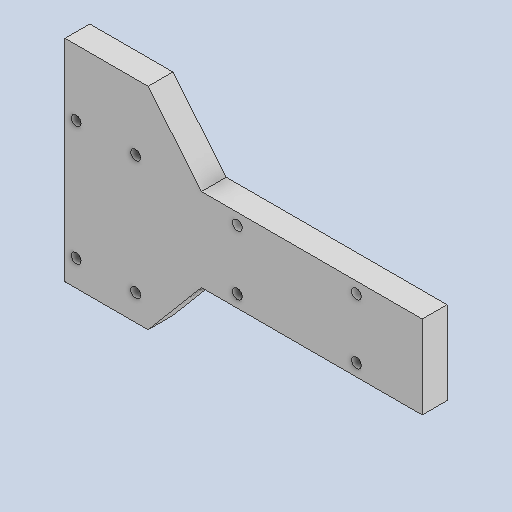
# Autodesk Inventor part: ConnectortoElbowSide
Saved by Autodesk Inventor 2025.2 (Build 292293000, 293)
## iProperties
Created: 2025-06-27
Part Number: ConnectortoElbowSide
Material: Generic
Document SubType Name: Modeling
Designer: ricoa
Density: 1 g/cm^3
Appearance: Default
Author: ricoa
Autodesk Inventor part; units mm, degrees
ref_plane "YZ Plane" through (0, 0, 0) normal (1, 0, 0) x (0, 1, 0)
ref_plane "XZ Plane" through (0, 0, 0) normal (0, 1, 0) x (-1, 0, 0)
ref_plane "XY Plane" through (0, 0, 0) normal (0, 0, 1) x (1, 0, 0)
sketch "Sketch1" plane through (0, 0, 0) normal (0, 0, 1) x (1, 0, 0)
  line L0 (-2, 0) -> (-2, 16.75) projected
  line L1 (-2, 16.75) -> (-44.5, 16.75) projected
  line L2 (-2, 0) -> (-44.5, 0) projected
  circle A0 centre (-39.25, 2.5) radius 1 projected
  circle A1 centre (-39.25, 14.5) radius 1 projected
  circle A2 centre (-15.25, 2.5) radius 1 projected
  circle A3 centre (-15.25, 14.5) radius 1 projected
  line L3 (-44.5, 16.75) -> (-46.5, 16.75)
  line L4 (-44.5, 0) -> (-46.5, 0)
  line L5 (-15.25, 14.5) -> (-8, 14.5)
  line L6 (-8, 16.75) -> (-8, 0)
  line L7 (-57.25, 29.75) -> (-74, 29.75) projected
  line L8 (-74, 29.75) -> (-74, -12.75) projected
  line L9 (-74, -12.75) -> (-57.25, -12.75) projected
  line L10 (-57.25, 29.75) -> (-57.25, -12.75)
  circle A4 centre (-59.75, -7.5) radius 1 projected
  circle A5 centre (-71.75, -7.5) radius 1 projected
  circle A6 centre (-59.75, 16.5) radius 1 projected
  circle A7 centre (-71.75, 16.5) radius 1 projected
  line L11 (-57.25, 29.75) -> (-46.5, 16.75)
  line L12 (-46.5, 0) -> (-57.25, -12.75)
  line L13 (-46.5, 0) -> (-44.5, 0)
  point P0 (0, 0)
  point P1 (-51.5, 16.75)
  dimension "d6" = 7.25
  constraints: 16 end point, 3 point on line, 2 horizontal, 2 perpendicular, 1 parallel
  measures "d6" distance of L5.start L5.end
extrude "Extrusion1" add sketch "Sketch1" along normal blind 5
body "Solid1"
